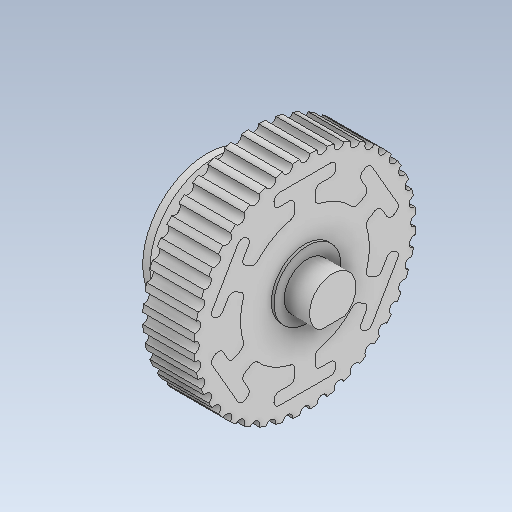
# Autodesk Inventor part: Rad ohne Antrieb
Saved by Autodesk Inventor 2026.4 (Build 304435030, 435C)
## iProperties
Created: 2026-11-20
Part Number: Rad ohne Antrieb
Material: Generisch
Document SubType Name: Modeling
Designer: weira
Density: 1 g/cm^3
Appearance: Vorgabe
Author: weira
Autodesk Inventor part; units mm, degrees
(part 1 of 2)
ref_plane "YZ Plane" through (0, 0, 0) normal (1, 0, 0) x (0, 1, 0)
ref_plane "XZ Plane" through (0, 0, 0) normal (0, 1, 0) x (-1, 0, 0)
ref_plane "XY Plane" through (0, 0, 0) normal (0, 0, 1) x (1, 0, 0)
sketch "Skizze1" plane through (0, 0, 0) normal (1, 0, 0) x (0, 1, 0)
  circle A0 centre (0, 0) radius 9.5511 construction
  line L0 (-27.1413, 20.191) -> (-18.5928, 20.191)
  line L1 (-18.5928, 20.191) -> (-18.5928, 11.6857)
  line L2 (-18.5928, 11.6857) -> (-27.1413, 11.6857)
  line L3 (-27.1413, 11.6857) -> (-27.1413, 20.191)
  circle A1 centre (0, 0) radius 8.6811 construction
  circle A2 centre (0, 0) radius 9.8211
  arc A3 (0.7095, 9.0476) -> (0.9041, 9.6681) centre (-0.61, 9.8021) ccw
  arc A4 (1.0279, 9.7672) -> (0.9041, 9.6681) centre (1.0264, 9.6422) ccw
  line L4 (0, 8.6811) -> (0, 7.1512) construction
  arc A5 (-0.9041, 9.6681) -> (-0.7095, 9.0476) centre (0.61, 9.8021) ccw
  arc A6 (-0.9041, 9.6681) -> (-1.0279, 9.7672) centre (-1.0264, 9.6422) ccw
  arc A7 (-0.7095, 9.0476) -> (0.7095, 9.0476) centre (0, 9.5511) ccw
  arc A8 (-2.0407, 9.6068) -> (-2.1278, 9.4743) centre (-2.0035, 9.4874) ccw
  arc A9 (-3.8474, 8.9155) -> (-3.9958, 8.9715) centre (-3.9557, 8.8531) ccw
  arc A10 (-2.1211, 8.824) -> (-2.1278, 9.4743) centre (-3.6092, 9.1339) ccw
  arc A11 (-3.8474, 8.9155) -> (-3.4706, 8.3855) centre (-2.4489, 9.5109) ccw
  arc A12 (-3.4706, 8.3855) -> (-2.1211, 8.824) centre (-2.9515, 9.0836) ccw
  arc A13 (-4.9094, 8.506) -> (-4.9513, 8.353) centre (-4.8372, 8.404) ccw
  arc A14 (-6.4142, 7.2902) -> (-6.5726, 7.2976) centre (-6.4979, 7.1974) ccw
  arc A15 (-4.744, 7.7367) -> (-4.9513, 8.353) centre (-6.2551, 7.5715) ccw
  arc A16 (-6.4142, 7.2902) -> (-5.892, 6.9026) centre (-5.2681, 8.2886) ccw
  arc A17 (-5.892, 6.9026) -> (-4.744, 7.7367) centre (-5.614, 7.727) ccw
  arc A18 (-7.2976, 6.5726) -> (-7.2902, 6.4142) centre (-7.1974, 6.4979) ccw
  arc A19 (-8.353, 4.9513) -> (-8.506, 4.9094) centre (-8.404, 4.8372) ccw
  arc A20 (-6.9026, 5.892) -> (-7.2902, 6.4142) centre (-8.2886, 5.2681) ccw
  arc A21 (-8.353, 4.9513) -> (-7.7367, 4.744) centre (-7.5715, 6.2551) ccw
  arc A22 (-7.7367, 4.744) -> (-6.9026, 5.892) centre (-7.727, 5.614) ccw
  arc A23 (-8.9715, 3.9958) -> (-8.9155, 3.8474) centre (-8.8531, 3.9557) ccw
  arc A24 (-9.4743, 2.1278) -> (-9.6068, 2.0407) centre (-9.4874, 2.0035) ccw
  arc A25 (-8.3855, 3.4706) -> (-8.9155, 3.8474) centre (-9.5109, 2.4489) ccw
  arc A26 (-9.4743, 2.1278) -> (-8.824, 2.1211) centre (-9.1339, 3.6092) ccw
  arc A27 (-8.824, 2.1211) -> (-8.3855, 3.4706) centre (-9.0836, 2.9515) ccw
  arc A28 (-9.7672, 1.0279) -> (-9.6681, 0.9041) centre (-9.6422, 1.0264) ccw
  arc A29 (-9.6681, -0.9041) -> (-9.7672, -1.0279) centre (-9.6422, -1.0264) ccw
  arc A30 (-9.0476, 0.7095) -> (-9.6681, 0.9041) centre (-9.8021, -0.61) ccw
  arc A31 (-9.6681, -0.9041) -> (-9.0476, -0.7095) centre (-9.8021, 0.61) ccw
  arc A32 (-9.0476, -0.7095) -> (-9.0476, 0.7095) centre (-9.5511, 0) ccw
  arc A33 (-9.6068, -2.0407) -> (-9.4743, -2.1278) centre (-9.4874, -2.0035) ccw
  arc A34 (-8.9155, -3.8474) -> (-8.9715, -3.9958) centre (-8.8531, -3.9557) ccw
  arc A35 (-8.824, -2.1211) -> (-9.4743, -2.1278) centre (-9.1339, -3.6092) ccw
  arc A36 (-8.9155, -3.8474) -> (-8.3855, -3.4706) centre (-9.5109, -2.4489) ccw
  arc A37 (-8.3855, -3.4706) -> (-8.824, -2.1211) centre (-9.0836, -2.9515) ccw
  arc A38 (-8.506, -4.9094) -> (-8.353, -4.9513) centre (-8.404, -4.8372) ccw
  arc A39 (-7.2902, -6.4142) -> (-7.2976, -6.5726) centre (-7.1974, -6.4979) ccw
  arc A40 (-7.7367, -4.744) -> (-8.353, -4.9513) centre (-7.5715, -6.2551) ccw
  arc A41 (-7.2902, -6.4142) -> (-6.9026, -5.892) centre (-8.2886, -5.2681) ccw
  arc A42 (-6.9026, -5.892) -> (-7.7367, -4.744) centre (-7.727, -5.614) ccw
  arc A43 (-6.5726, -7.2976) -> (-6.4142, -7.2902) centre (-6.4979, -7.1974) ccw
  arc A44 (-4.9513, -8.353) -> (-4.9094, -8.506) centre (-4.8372, -8.404) ccw
  arc A45 (-5.892, -6.9026) -> (-6.4142, -7.2902) centre (-5.2681, -8.2886) ccw
  arc A46 (-4.9513, -8.353) -> (-4.744, -7.7367) centre (-6.2551, -7.5715) ccw
  arc A47 (-4.744, -7.7367) -> (-5.892, -6.9026) centre (-5.614, -7.727) ccw
  arc A48 (-3.9958, -8.9715) -> (-3.8474, -8.9155) centre (-3.9557, -8.8531) ccw
  arc A49 (-2.1278, -9.4743) -> (-2.0407, -9.6068) centre (-2.0035, -9.4874) ccw
  arc A50 (-3.4706, -8.3855) -> (-3.8474, -8.9155) centre (-2.4489, -9.5109) ccw
  arc A51 (-2.1278, -9.4743) -> (-2.1211, -8.824) centre (-3.6092, -9.1339) ccw
  arc A52 (-2.1211, -8.824) -> (-3.4706, -8.3855) centre (-2.9515, -9.0836) ccw
  arc A53 (-1.0279, -9.7672) -> (-0.9041, -9.6681) centre (-1.0264, -9.6422) ccw
  arc A54 (0.9041, -9.6681) -> (1.0279, -9.7672) centre (1.0264, -9.6422) ccw
  arc A55 (-0.7095, -9.0476) -> (-0.9041, -9.6681) centre (0.61, -9.8021) ccw
  arc A56 (0.9041, -9.6681) -> (0.7095, -9.0476) centre (-0.61, -9.8021) ccw
  arc A57 (0.7095, -9.0476) -> (-0.7095, -9.0476) centre (0, -9.5511) ccw
  arc A58 (2.0407, -9.6068) -> (2.1278, -9.4743) centre (2.0035, -9.4874) ccw
  arc A59 (3.8474, -8.9155) -> (3.9958, -8.9715) centre (3.9557, -8.8531) ccw
  arc A60 (2.1211, -8.824) -> (2.1278, -9.4743) centre (3.6092, -9.1339) ccw
  arc A61 (3.8474, -8.9155) -> (3.4706, -8.3855) centre (2.4489, -9.5109) ccw
  arc A62 (3.4706, -8.3855) -> (2.1211, -8.824) centre (2.9515, -9.0836) ccw
  arc A63 (4.9094, -8.506) -> (4.9513, -8.353) centre (4.8372, -8.404) ccw
  arc A64 (6.4142, -7.2902) -> (6.5726, -7.2976) centre (6.4979, -7.1974) ccw
  arc A65 (4.744, -7.7367) -> (4.9513, -8.353) centre (6.2551, -7.5715) ccw
  arc A66 (6.4142, -7.2902) -> (5.892, -6.9026) centre (5.2681, -8.2886) ccw
  arc A67 (5.892, -6.9026) -> (4.744, -7.7367) centre (5.614, -7.727) ccw
  arc A68 (7.2976, -6.5726) -> (7.2902, -6.4142) centre (7.1974, -6.4979) ccw
  arc A69 (8.353, -4.9513) -> (8.506, -4.9094) centre (8.404, -4.8372) ccw
  arc A70 (6.9026, -5.892) -> (7.2902, -6.4142) centre (8.2886, -5.2681) ccw
  arc A71 (8.353, -4.9513) -> (7.7367, -4.744) centre (7.5715, -6.2551) ccw
  arc A72 (7.7367, -4.744) -> (6.9026, -5.892) centre (7.727, -5.614) ccw
  arc A73 (8.9715, -3.9958) -> (8.9155, -3.8474) centre (8.8531, -3.9557) ccw
  arc A74 (9.4743, -2.1278) -> (9.6068, -2.0407) centre (9.4874, -2.0035) ccw
  arc A75 (8.3855, -3.4706) -> (8.9155, -3.8474) centre (9.5109, -2.4489) ccw
  arc A76 (9.4743, -2.1278) -> (8.824, -2.1211) centre (9.1339, -3.6092) ccw
  arc A77 (8.824, -2.1211) -> (8.3855, -3.4706) centre (9.0836, -2.9515) ccw
  arc A78 (9.7672, -1.0279) -> (9.6681, -0.9041) centre (9.6422, -1.0264) ccw
  arc A79 (9.6681, 0.9041) -> (9.7672, 1.0279) centre (9.6422, 1.0264) ccw
  arc A80 (9.0476, -0.7095) -> (9.6681, -0.9041) centre (9.8021, 0.61) ccw
  arc A81 (9.6681, 0.9041) -> (9.0476, 0.7095) centre (9.8021, -0.61) ccw
  arc A82 (9.0476, 0.7095) -> (9.0476, -0.7095) centre (9.5511, 0) ccw
  arc A83 (9.6068, 2.0407) -> (9.4743, 2.1278) centre (9.4874, 2.0035) ccw
  arc A84 (8.9155, 3.8474) -> (8.9715, 3.9958) centre (8.8531, 3.9557) ccw
  arc A85 (8.824, 2.1211) -> (9.4743, 2.1278) centre (9.1339, 3.6092) ccw
  arc A86 (8.9155, 3.8474) -> (8.3855, 3.4706) centre (9.5109, 2.4489) ccw
  arc A87 (8.3855, 3.4706) -> (8.824, 2.1211) centre (9.0836, 2.9515) ccw
  arc A88 (8.506, 4.9094) -> (8.353, 4.9513) centre (8.404, 4.8372) ccw
  arc A89 (7.2902, 6.4142) -> (7.2976, 6.5726) centre (7.1974, 6.4979) ccw
  arc A90 (7.7367, 4.744) -> (8.353, 4.9513) centre (7.5715, 6.2551) ccw
  arc A91 (7.2902, 6.4142) -> (6.9026, 5.892) centre (8.2886, 5.2681) ccw
  arc A92 (6.9026, 5.892) -> (7.7367, 4.744) centre (7.727, 5.614) ccw
  arc A93 (6.5726, 7.2976) -> (6.4142, 7.2902) centre (6.4979, 7.1974) ccw
  arc A94 (4.9513, 8.353) -> (4.9094, 8.506) centre (4.8372, 8.404) ccw
  arc A95 (5.892, 6.9026) -> (6.4142, 7.2902) centre (5.2681, 8.2886) ccw
  arc A96 (4.9513, 8.353) -> (4.744, 7.7367) centre (6.2551, 7.5715) ccw
  arc A97 (4.744, 7.7367) -> (5.892, 6.9026) centre (5.614, 7.727) ccw
  arc A98 (3.9958, 8.9715) -> (3.8474, 8.9155) centre (3.9557, 8.8531) ccw
  arc A99 (2.1278, 9.4743) -> (2.0407, 9.6068) centre (2.0035, 9.4874) ccw
  arc A100 (3.4706, 8.3855) -> (3.8474, 8.9155) centre (2.4489, 9.5109) ccw
  arc A101 (2.1278, 9.4743) -> (2.1211, 8.824) centre (3.6092, 9.1339) ccw
  arc A102 (2.1211, 8.824) -> (3.4706, 8.3855) centre (2.9515, 9.0836) ccw
  circle A103 centre (0, 0) radius 12.0811
  point P0 (-2.6826, 8.2562)
  point P1 (-5.1026, 7.0232)
  point P2 (-7.0232, 5.1026)
  point P3 (-8.2562, 2.6826)
  point P4 (-8.6811, 0)
  point P5 (-8.2562, -2.6826)
  point P6 (-7.0232, -5.1026)
  point P7 (-5.1026, -7.0232)
  point P8 (-2.6826, -8.2562)
  point P9 (0, -8.6811)
  point P10 (2.6826, -8.2562)
  point P11 (5.1026, -7.0232)
  point P12 (7.0232, -5.1026)
  point P13 (8.2562, -2.6826)
  point P14 (8.6811, 0)
  point P15 (8.2562, 2.6826)
  point P16 (7.0232, 5.1026)
  point P17 (5.1026, 7.0232)
  point P18 (2.6826, 8.2562)
  point P19 (-22.511, 9.9251)
  point P20 (-23.5238, 9.7647)
  point P21 (-25.4789, 9.1295)
  point P22 (-26.3926, 8.6639)
  point P23 (-28.0557, 7.4556)
  point P24 (-28.7808, 6.7305)
  point P25 (-29.9891, 5.0674)
  point P26 (-30.4547, 4.1537)
  point P27 (-31.0899, 2.1986)
  point P28 (-31.2503, 1.1858)
  point P29 (-31.2503, -0.8699)
  point P30 (-31.0899, -1.8827)
  point P31 (-30.4547, -3.8378)
  point P32 (-29.9891, -4.7515)
  point P33 (-28.7808, -6.4146)
  point P34 (-28.0557, -7.1397)
  point P35 (-26.3926, -8.348)
  point P36 (-25.4789, -8.8135)
  point P37 (-23.5238, -9.4488)
  point P38 (-22.511, -9.6092)
  point P39 (-20.4553, -9.6092)
  point P40 (-19.4425, -9.4488)
  point P41 (-17.4874, -8.8135)
  point P42 (-16.5737, -8.348)
  point P43 (-14.9106, -7.1397)
  point P44 (-14.1855, -6.4146)
  point P45 (-12.9772, -4.7515)
  point P46 (-12.5117, -3.8378)
  point P47 (-11.8764, -1.8827)
  point P48 (-11.716, -0.8699)
  point P49 (-11.716, 1.1858)
  point P50 (-11.8764, 2.1986)
  point P51 (-12.5117, 4.1537)
  point P52 (-12.9772, 5.0674)
  point P53 (-14.1855, 6.7305)
  point P54 (-14.9106, 7.4556)
  point P55 (-16.5737, 8.6639)
  point P56 (-17.4874, 9.1295)
  point P57 (-19.4425, 9.7647)
  point P58 (-1.0279, 9.7672)
  point P59 (-2.0407, 9.6068)
  point P60 (-3.9958, 8.9715)
  point P61 (-4.9094, 8.506)
  point P62 (-6.5726, 7.2976)
  point P63 (-7.2976, 6.5726)
  point P64 (-8.506, 4.9094)
  point P65 (-8.9715, 3.9958)
  point P66 (-9.6068, 2.0407)
  point P67 (-9.7672, 1.0279)
  point P68 (-9.7672, -1.0279)
  point P69 (-9.6068, -2.0407)
  point P70 (-8.9715, -3.9958)
  point P71 (-8.506, -4.9094)
  point P72 (-7.2976, -6.5726)
  point P73 (-6.5726, -7.2976)
  point P74 (-4.9094, -8.506)
  point P75 (-3.9958, -8.9715)
  point P76 (-2.0407, -9.6068)
  point P77 (-1.0279, -9.7672)
  point P78 (1.0279, -9.7672)
  point P79 (2.0407, -9.6068)
  point P80 (3.9958, -8.9715)
  point P81 (4.9094, -8.506)
  point P82 (6.5726, -7.2976)
  point P83 (7.2976, -6.5726)
  point P84 (8.506, -4.9094)
  point P85 (8.9715, -3.9958)
  point P86 (9.6068, -2.0407)
  point P87 (9.7672, -1.0279)
  point P88 (9.7672, 1.0279)
  point P89 (9.6068, 2.0407)
  point P90 (8.9715, 3.9958)
  point P91 (8.506, 4.9094)
  point P92 (7.2976, 6.5726)
  point P93 (6.5726, 7.2976)
  point P94 (4.9094, 8.506)
  point P95 (3.9958, 8.9715)
  point P96 (2.0407, 9.6068)
  dimension "d2" = 19.1022
  dimension "d3" = 1.14
  dimension "d4" = 0.61
  dimension "d5" = 0.25
  dimension "d6" = 360
  dimension "d7" = 3.4
  constraints: 220 point on circle, 101 centre point, 5 coincident, 5 symmetric about line, 2 end point, 2 vertical alignment, 1 vertical, 353 other
  measures "d4" horizontal distance of A3.centre A7.centre
  measures "d5" diameter of A4
extrude "Extrusion1" add sketch "Skizze1" along normal mid plane 6.2 contours A79 A81 A82 A80 A78 A2 A74 A76 A77 A75 A73 A69 A71 A72 A70 A68 A64 A66 A67 A65 A63 A59 A61 A62 A60 A58 A54 A56 A57 A55 A53 A49 A51 A52 A50 A48 A44 A46 A47 A45 A43 A39 A41 A42 A40 A38 A34 A36 A37 A35 A33 A29 A31 A32 A30 A28 A24 A26 A27 A25 A23 A19 A21 A22 A20 A18 A14 A16 A17 A15 A13 A9 A11 A12 A10 A8 A6 A5 A7 A3 A4 A99 A101 A102 A100 A98 A94 A96 A97 A95 A93 A89 A91 A92 A90 A88 A84 A86 A87 A85 A83
sketch "Skizze2" plane through (-3.1, 0, 0) normal (-1, 0, 0) x (0, 0, 1)
  circle A0 centre (0, 0) radius 9.825
  circle A1 centre (0, 0) radius 12.5
  dimension "d14" = 19.65
  dimension "d15" = 25
  constraints: 2 centre point, 2 coincident
  measures "d14" diameter of A0
  measures "d15" diameter of A1
extrude "Extrusion2" add sketch "Skizze2" along normal blind 1.4 contours A0 | A1
mirror "Spiegeln1" about plane through (0, 0, 0) normal (1, 0, 0) of "Extrusion2"
sketch "Skizze5" plane through (4.5, 0, 0) normal (1, 0, 0) x (0, 0, -1)
  circle A0 centre (0, 0) radius 12.5 projected
  circle A1 centre (0, 0) radius 20
  dimension "d28" = 40
  constraints: 1 centre point, 1 coincident
  measures "d28" diameter of A1
extrude "Extrusion5" add sketch "Skizze5" along normal blind 10 contours A0 | A1
sketch "Skizze6" plane through (14.5, 0, 0) normal (1, 0, 0) x (0, 0, -1)
  line L0 (-5, -6) -> (5, -6)
  line L1 (5, -6) -> (5, 6)
  line L2 (5, 6) -> (-5, 6)
  line L3 (-5, 6) -> (-5, -6)
  line L4 (-5, -6) -> (5, 6) construction
  line L5 (5, -6) -> (-5, 6) construction
  circle A0 centre (0, 0) radius 7.8102
  circle A1 centre (0, 0) radius 8.5
  dimension "d33" = 15.6205
  dimension "d31" = 12
  dimension "d32" = 10
  dimension "d34" = 17
  constraints: 12 end point, 2 coincident, 2 midpoint, 2 parallel, 1 centre point, 1 horizontal, 1 perpendicular, 3 other
  measures "d31" distance of L2.end L0.start
  measures "d32" distance of L1.end L2.end
  measures "d34" diameter of A1
extrude "Extrusion6" cut sketch "Skizze6" against normal blind 8.8 contours L3 L2 L1 L0 | A0 L3 | L0 A0 | L1 A0 | A0 L2 | A1
sketch "Skizze7" plane through (-4.5, 0, 0) normal (-1, 0, 0) x (0, 0, 1)
  arc A0 (2.0768, -37.6136) -> (2.0768, -39.8496) centre (1.0768, -38.7316) ccw
  arc A1 (-2.7232, -41.142) -> (-2.7232, -36.3212) centre (1.0768, -38.7316) ccw
  line L0 (-2.7232, -36.3212) -> (-2.7232, -41.142)
  circle A2 centre (0, 0) radius 12.5 projected
  arc A3 (1, 1.118) -> (1, -1.118) centre (0, 0) ccw
  arc A4 (-3.8, -2.4104) -> (-3.8, 2.4104) centre (0, 0) ccw
  line L1 (-3.8, 2.4104) -> (-3.8, -2.4104)
  constraints: 8 point on circle, 4 centre point, 4 end point
extrude "Extrusion7" cut sketch "Skizze7" against normal blind 8.2 contours L1 A4
extrude "Extrusion8" add sketch "Skizze7" against normal blind 8.2 separate body contours L1 A4
extrude "Extrusion9" add sketch "Skizze7" along normal blind 5.5 contours L1 A4 bodies 2
sketch "Skizze8" plane through (5.7, 0, 0) normal (1, 0, 0) x (0, 0, -1)
  arc A0 (0.2064, 25.9208) -> (2.4424, 25.9208) centre (1.3244, 24.9208) ccw
  line L0 (2.4424, 25.9208) -> (0.2064, 25.9208)
  arc A1 (1, 1.118) -> (1, -1.118) centre (0, 0) ccw
  line L1 (1, -1.118) -> (1, 1.118)
  constraints: 4 end point, 4 point on circle, 2 centre point
extrude "Extrusion10" cut sketch "Skizze8" against normal blind 10.2 contours L1 A1 bodies 1 2
sketch "Skizze9" plane through (-4.5, 0, 0) normal (-1, 0, 0) x (0, 0, 1)
  line L0 (-3.8, 2.4104) -> (-3.8, -2.4104) projected
  arc A0 (-3.8, -2.4104) -> (-3.8, 2.4104) centre (0, 0) ccw projected
  circle A1 centre (0.2217, 0) radius 6.5
  arc A2 (-3.8, -2.4104) -> (-3.8, 2.4104) centre (0, 0) ccw projected
  dimension "d45" = 13
  constraints: 1 centre point
  measures "d45" diameter of A1
extrude "Extrusion11" add sketch "Skizze9" along normal blind 0.5 bodies 1
sketch "Skizze12" plane through (4.5, 0, 0) normal (-1, 0, 0) x (0, 0, 1)
  circle A0 centre (0, 0) radius 12.5 projected
  line L0 (15.5, 2) -> (10.5, 2)
  line L1 (10.5, 2) -> (10.5, -2)
  line L2 (10.5, -2) -> (15.5, -2)
  line L3 (15.5, -2) -> (15.5, 2)
  line L4 (21.7574, 0) -> (-22.368, 0) construction
  line L5 (-31.1931, 0) -> (30.5824, 0) projected
  line L6 (17.9, 6) -> (15.5, 6)
  line L7 (15.5, 6) -> (15.5, -6)
  line L8 (15.5, -6) -> (17.9, -6)
  line L9 (17.9, -6) -> (17.9, 6)
  line L10 (9.4821, 12.4234) -> (6.0179, 14.4234)
  line L11 (3.7538, 18.5019) -> (2.5538, 16.4234)
  line L12 (6.0179, 14.4234) -> (3.5179, 10.0933)
  line L13 (6.9821, 8.0933) -> (9.4821, 12.4234)
  line L14 (12.9462, 10.4234) -> (14.1462, 12.5019)
  line L15 (2.5538, 16.4234) -> (12.9462, 10.4234)
  line L16 (14.1462, 12.5019) -> (3.7538, 18.5019)
  line L17 (3.5179, 10.0933) -> (6.9821, 8.0933)
  line L18 (-6.0179, 14.4234) -> (-9.4821, 12.4234)
  line L19 (-14.1462, 12.5019) -> (-12.9462, 10.4234)
  line L20 (-9.4821, 12.4234) -> (-6.9821, 8.0933)
  line L21 (-3.5179, 10.0933) -> (-6.0179, 14.4234)
  line L22 (-2.5538, 16.4234) -> (-3.7538, 18.5019)
  line L23 (-12.9462, 10.4234) -> (-2.5538, 16.4234)
  line L24 (-3.7538, 18.5019) -> (-14.1462, 12.5019)
  line L25 (-6.9821, 8.0933) -> (-3.5179, 10.0933)
  line L26 (-15.5, 2) -> (-15.5, -2)
  line L27 (-17.9, -6) -> (-15.5, -6)
  line L28 (-15.5, -2) -> (-10.5, -2)
  line L29 (-10.5, 2) -> (-15.5, 2)
  line L30 (-15.5, 6) -> (-17.9, 6)
  line L31 (-15.5, -6) -> (-15.5, 6)
  line L32 (-17.9, 6) -> (-17.9, -6)
  line L33 (-10.5, -2) -> (-10.5, 2)
  line L34 (-9.4821, -12.4234) -> (-6.0179, -14.4234)
  line L35 (-3.7538, -18.5019) -> (-2.5538, -16.4234)
  line L36 (-6.0179, -14.4234) -> (-3.5179, -10.0933)
  line L37 (-6.9821, -8.0933) -> (-9.4821, -12.4234)
  line L38 (-12.9462, -10.4234) -> (-14.1462, -12.5019)
  line L39 (-2.5538, -16.4234) -> (-12.9462, -10.4234)
  line L40 (-14.1462, -12.5019) -> (-3.7538, -18.5019)
  line L41 (-3.5179, -10.0933) -> (-6.9821, -8.0933)
  line L42 (6.0179, -14.4234) -> (9.4821, -12.4234)
  line L43 (14.1462, -12.5019) -> (12.9462, -10.4234)
  line L44 (9.4821, -12.4234) -> (6.9821, -8.0933)
  line L45 (3.5179, -10.0933) -> (6.0179, -14.4234)
  line L46 (2.5538, -16.4234) -> (3.7538, -18.5019)
  line L47 (12.9462, -10.4234) -> (2.5538, -16.4234)
  line L48 (3.7538, -18.5019) -> (14.1462, -12.5019)
  line L49 (6.9821, -8.0933) -> (3.5179, -10.0933)
  circle A1 centre (0, 0) radius 20 projected
  circle A2 centre (0, 0) radius 12.5 projected
  point P0 (10.8787, 18.8424)
  point P1 (-10.8787, 18.8424)
  point P2 (-21.7574, 0)
  point P3 (-10.8787, -18.8424)
  point P4 (10.8787, -18.8424)
  point P5 (-15.5, 2)
  point P6 (-12.339, 2)
  point P7 (-7.9015, 9.6859)
  point P8 (-9.4821, 12.4234)
  point P9 (-6.0179, 14.4234)
  point P10 (-4.4374, 11.6859)
  point P11 (4.4374, 11.6859)
  point P12 (6.0179, 14.4234)
  point P13 (9.4821, 12.4234)
  point P14 (7.9015, 9.6859)
  point P15 (12.339, 2)
  point P16 (15.5, -2)
  point P17 (12.339, -2)
  point P18 (7.9015, -9.6859)
  point P19 (9.4821, -12.4234)
  point P20 (6.0179, -14.4234)
  point P21 (4.4374, -11.6859)
  point P22 (-4.4374, -11.6859)
  point P23 (-6.0179, -14.4234)
  point P24 (-9.4821, -12.4234)
  point P25 (-7.9015, -9.6859)
  point P26 (-12.339, -2)
  point P27 (-15.5, -2)
  dimension "d53" = 4
  dimension "d54" = 3
  dimension "d55" = 2
  dimension "d56" = 0
  dimension "d57" = 5
  dimension "d58" = 2.4
  dimension "d59" = 0
  dimension "d60" = 12
  dimension "d61" = 6
  dimension "d64" = 360
  constraints: 98 end point, 4 parallel, 3 horizontal, 2 perpendicular, 103 other
  measures "d53" distance between parallel lines of L2 L0
  measures "d54" distance edge to line of A0 L3
  measures "d55" distance between parallel lines of L4 L2
  measures "d56" distance between parallel lines of L5 L4
  measures "d57" distance of L1.end L2.end
  measures "d58" distance between parallel lines of L7 L9
  measures "d59" distance between parallel lines of L3 L7
  measures "d60" distance between parallel lines of L8 L6
  measures "d61" distance between parallel lines of L4 L8
extrude "Extrusion12" cut sketch "Skizze12" against normal through all contours A0 L13 L15 L14 L16 L11 L12 L21 L23 L22 L24 L19 L20 L29 L31 L30 L32 L5 A1 L9 L6 L7 L0 | L2 L7 L8 L9 L5 A1 L32 L27 L31 L28 A0 L37 L39 L38 L40 L35 L36 L45 L47 L46 L48 L43 L44 bodies 1
fillet "Rundung1" radius 1 8 edges at (9.5, 18.5019, 3.7538) (9.5, 16.4234, 2.5538) (9.5, 12.5019, 14.1462) (9.5, 10.4234, 12.9462) (9.5, 14.4234, 6.0179) (9.5, 11.6859, 4.4374) (9.5, 9.6859, 7.9015) (9.5, 12.4234, 9.4821)
pattern_circular "Runde Anordnung1" count 6 over 360 about axis through (-10, 0, 0) along (1, 0, 0) of "Rundung1"
sketch "Skizze13" plane through (4.5, 0, 0) normal (-1, 0, 0) x (0, 0, 1)
  circle A0 centre (0, 0) radius 20
  arc A1 (12.0801, 10.9234) -> (13.4462, 11.2894) centre (12.5801, 11.7894) ccw projected
  line L0 (13.4462, 11.2894) -> (13.6462, 11.6358) projected
  arc A2 (13.6462, 11.6358) -> (13.2801, 13.0019) centre (12.7801, 12.1358) ccw projected
  line L1 (13.2801, 13.0019) -> (4.6199, 18.0019) projected
  arc A3 (4.6199, 18.0019) -> (3.2538, 17.6358) centre (4.1199, 17.1358) ccw projected
  line L2 (3.2538, 17.6358) -> (3.0538, 17.2894) projected
  arc A4 (3.0538, 17.2894) -> (3.4199, 15.9234) centre (3.9199, 16.7894) ccw projected
  arc A5 (5.5179, 13.5574) -> (5.1519, 14.9234) centre (4.6519, 14.0574) ccw projected
  line L3 (5.5179, 13.5574) -> (4.8492, 12.399) projected
  arc A6 (3.6881, 11.9435) -> (4.8492, 12.399) centre (3.9831, 12.899) ccw projected
  arc A7 (8.4994, 9.1658) -> (3.6881, 11.9435) centre (0, 0) ccw projected
  arc A8 (8.3133, 10.399) -> (8.4994, 9.1658) centre (9.1793, 9.899) ccw projected
  line L4 (8.3133, 10.399) -> (8.9821, 11.5574) projected
  arc A9 (10.3481, 11.9234) -> (8.9821, 11.5574) centre (9.8481, 11.0574) ccw projected
  arc A10 (-3.4199, 15.9234) -> (-3.0538, 17.2894) centre (-3.9199, 16.7894) ccw projected
  line L5 (-3.0538, 17.2894) -> (-3.2538, 17.6358) projected
  arc A11 (-3.2538, 17.6358) -> (-4.6199, 18.0019) centre (-4.1199, 17.1358) ccw projected
  line L6 (-4.6199, 18.0019) -> (-13.2801, 13.0019) projected
  arc A12 (-13.2801, 13.0019) -> (-13.6462, 11.6358) centre (-12.7801, 12.1358) ccw projected
  line L7 (-13.6462, 11.6358) -> (-13.4462, 11.2894) projected
  arc A13 (-13.4462, 11.2894) -> (-12.0801, 10.9234) centre (-12.5801, 11.7894) ccw projected
  arc A14 (-8.9821, 11.5574) -> (-10.3481, 11.9234) centre (-9.8481, 11.0574) ccw projected
  line L8 (-8.9821, 11.5574) -> (-8.3133, 10.399) projected
  arc A15 (-8.4994, 9.1658) -> (-8.3133, 10.399) centre (-9.1793, 9.899) ccw projected
  arc A16 (-3.6881, 11.9435) -> (-8.4994, 9.1658) centre (0, 0) ccw projected
  arc A17 (-4.8492, 12.399) -> (-3.6881, 11.9435) centre (-3.9831, 12.899) ccw projected
  line L9 (-4.8492, 12.399) -> (-5.5179, 13.5574) projected
  arc A18 (-5.1519, 14.9234) -> (-5.5179, 13.5574) centre (-4.6519, 14.0574) ccw projected
  arc A19 (-15.5, 5) -> (-16.5, 6) centre (-16.5, 5) ccw projected
  line L10 (-16.5, 6) -> (-16.9, 6) projected
  arc A20 (-16.9, 6) -> (-17.9, 5) centre (-16.9, 5) ccw projected
  line L11 (-17.9, 5) -> (-17.9, -5) projected
  arc A21 (-17.9, -5) -> (-16.9, -6) centre (-16.9, -5) ccw projected
  line L12 (-16.9, -6) -> (-16.5, -6) projected
  arc A22 (-16.5, -6) -> (-15.5, -5) centre (-16.5, -5) ccw projected
  arc A23 (-14.5, -2) -> (-15.5, -3) centre (-14.5, -3) ccw projected
  line L13 (-14.5, -2) -> (-13.1624, -2) projected
  arc A24 (-12.1875, -2.7778) -> (-13.1624, -2) centre (-13.1624, -3) ccw projected
  arc A25 (-12.1875, 2.7778) -> (-12.1875, -2.7778) centre (0, 0) ccw projected
  arc A26 (-13.1624, 2) -> (-12.1875, 2.7778) centre (-13.1624, 3) ccw projected
  line L14 (-13.1624, 2) -> (-14.5, 2) projected
  arc A27 (-15.5, 3) -> (-14.5, 2) centre (-14.5, 3) ccw projected
  arc A28 (-12.0801, -10.9234) -> (-13.4462, -11.2894) centre (-12.5801, -11.7894) ccw projected
  line L15 (-13.4462, -11.2894) -> (-13.6462, -11.6358) projected
  arc A29 (-13.6462, -11.6358) -> (-13.2801, -13.0019) centre (-12.7801, -12.1358) ccw projected
  line L16 (-13.2801, -13.0019) -> (-4.6199, -18.0019) projected
  arc A30 (-4.6199, -18.0019) -> (-3.2538, -17.6358) centre (-4.1199, -17.1358) ccw projected
  line L17 (-3.2538, -17.6358) -> (-3.0538, -17.2894) projected
  arc A31 (-3.0538, -17.2894) -> (-3.4199, -15.9234) centre (-3.9199, -16.7894) ccw projected
  arc A32 (-5.5179, -13.5574) -> (-5.1519, -14.9234) centre (-4.6519, -14.0574) ccw projected
  line L18 (-5.5179, -13.5574) -> (-4.8492, -12.399) projected
  arc A33 (-3.6881, -11.9435) -> (-4.8492, -12.399) centre (-3.9831, -12.899) ccw projected
  arc A34 (-8.4994, -9.1658) -> (-3.6881, -11.9435) centre (0, 0) ccw projected
  arc A35 (-8.3133, -10.399) -> (-8.4994, -9.1658) centre (-9.1793, -9.899) ccw projected
  line L19 (-8.3133, -10.399) -> (-8.9821, -11.5574) projected
  arc A36 (-10.3481, -11.9234) -> (-8.9821, -11.5574) centre (-9.8481, -11.0574) ccw projected
  arc A37 (3.4199, -15.9234) -> (3.0538, -17.2894) centre (3.9199, -16.7894) ccw projected
  line L20 (3.0538, -17.2894) -> (3.2538, -17.6358) projected
  arc A38 (3.2538, -17.6358) -> (4.6199, -18.0019) centre (4.1199, -17.1358) ccw projected
  line L21 (4.6199, -18.0019) -> (13.2801, -13.0019) projected
  arc A39 (13.2801, -13.0019) -> (13.6462, -11.6358) centre (12.7801, -12.1358) ccw projected
  line L22 (13.6462, -11.6358) -> (13.4462, -11.2894) projected
  arc A40 (13.4462, -11.2894) -> (12.0801, -10.9234) centre (12.5801, -11.7894) ccw projected
  arc A41 (8.9821, -11.5574) -> (10.3481, -11.9234) centre (9.8481, -11.0574) ccw projected
  line L23 (8.9821, -11.5574) -> (8.3133, -10.399) projected
  arc A42 (8.4994, -9.1658) -> (8.3133, -10.399) centre (9.1793, -9.899) ccw projected
  arc A43 (3.6881, -11.9435) -> (8.4994, -9.1658) centre (0, 0) ccw projected
  arc A44 (4.8492, -12.399) -> (3.6881, -11.9435) centre (3.9831, -12.899) ccw projected
  line L24 (4.8492, -12.399) -> (5.5179, -13.5574) projected
  arc A45 (5.1519, -14.9234) -> (5.5179, -13.5574) centre (4.6519, -14.0574) ccw projected
  arc A46 (15.5, -5) -> (16.5, -6) centre (16.5, -5) ccw projected
  line L25 (16.5, -6) -> (16.9, -6) projected
  arc A47 (16.9, -6) -> (17.9, -5) centre (16.9, -5) ccw projected
  line L26 (17.9, -5) -> (17.9, 5) projected
  arc A48 (17.9, 5) -> (16.9, 6) centre (16.9, 5) ccw projected
  line L27 (16.9, 6) -> (16.5, 6) projected
  arc A49 (16.5, 6) -> (15.5, 5) centre (16.5, 5) ccw projected
  arc A50 (14.5, 2) -> (15.5, 3) centre (14.5, 3) ccw projected
  line L28 (14.5, 2) -> (13.1624, 2) projected
  arc A51 (12.1875, 2.7778) -> (13.1624, 2) centre (13.1624, 3) ccw projected
  arc A52 (12.1875, -2.7778) -> (12.1875, 2.7778) centre (0, 0) ccw projected
  arc A53 (13.1624, -2) -> (12.1875, -2.7778) centre (13.1624, -3) ccw projected
  line L29 (13.1624, -2) -> (14.5, -2) projected
  arc A54 (15.5, -3) -> (14.5, -2) centre (14.5, -3) ccw projected
  circle A55 centre (0, 0) radius 12.5 projected
  circle A56 centre (20, 0) radius 1
  circle A57 centre (19.7538, 3.1287) radius 1
  circle A58 centre (19.0211, 6.1803) radius 1
  circle A59 centre (17.8201, 9.0798) radius 1
  circle A60 centre (16.1803, 11.7557) radius 1
  circle A61 centre (14.1421, 14.1421) radius 1
  circle A62 centre (11.7557, 16.1803) radius 1
  circle A63 centre (9.0798, 17.8201) radius 1
  circle A64 centre (6.1803, 19.0211) radius 1
  circle A65 centre (3.1287, 19.7538) radius 1
  circle A66 centre (0, 20) radius 1
  circle A67 centre (-3.1287, 19.7538) radius 1
  circle A68 centre (-6.1803, 19.0211) radius 1
  circle A69 centre (-9.0798, 17.8201) radius 1
  circle A70 centre (-11.7557, 16.1803) radius 1
  circle A71 centre (-14.1421, 14.1421) radius 1
  circle A72 centre (-16.1803, 11.7557) radius 1
  circle A73 centre (-17.8201, 9.0798) radius 1
  circle A74 centre (-19.0211, 6.1803) radius 1
  circle A75 centre (-19.7538, 3.1287) radius 1
  circle A76 centre (-20, 0) radius 1
  circle A77 centre (-19.7538, -3.1287) radius 1
  circle A78 centre (-19.0211, -6.1803) radius 1
  circle A79 centre (-17.8201, -9.0798) radius 1
  circle A80 centre (-16.1803, -11.7557) radius 1
  circle A81 centre (-14.1421, -14.1421) radius 1
  circle A82 centre (-11.7557, -16.1803) radius 1
  circle A83 centre (-9.0798, -17.8201) radius 1
  circle A84 centre (-6.1803, -19.0211) radius 1
  circle A85 centre (-3.1287, -19.7538) radius 1
  circle A86 centre (0, -20) radius 1
  circle A87 centre (3.1287, -19.7538) radius 1
  circle A88 centre (6.1803, -19.0211) radius 1
  circle A89 centre (9.0798, -17.8201) radius 1
  circle A90 centre (11.7557, -16.1803) radius 1
  circle A91 centre (14.1421, -14.1421) radius 1
  circle A92 centre (16.1803, -11.7557) radius 1
  circle A93 centre (17.8201, -9.0798) radius 1
  circle A94 centre (19.0211, -6.1803) radius 1
  circle A95 centre (19.7538, -3.1287) radius 1
  line L30 (3.4199, 15.9234) -> (5.1519, 14.9234) projected
  line L31 (10.3481, 11.9234) -> (12.0801, 10.9234) projected
  line L32 (15.5, 5) -> (15.5, 3) projected
  line L33 (15.5, -3) -> (15.5, -5) projected
  line L34 (12.0801, -10.9234) -> (10.3481, -11.9234) projected
  line L35 (5.1519, -14.9234) -> (3.4199, -15.9234) projected
  line L36 (-3.4199, -15.9234) -> (-5.1519, -14.9234) projected
  line L37 (-10.3481, -11.9234) -> (-12.0801, -10.9234) projected
  line L38 (-15.5, -5) -> (-15.5, -3) projected
  line L39 (-15.5, 3) -> (-15.5, 5) projected
  line L40 (-12.0801, 10.9234) -> (-10.3481, 11.9234) projected
  line L41 (-5.1519, 14.9234) -> (-3.4199, 15.9234) projected
  point P0 (19.5727, -4.1122)
  point P1 (19.8855, -2.1374)
  point P2 (19.975, -0.9997)
  point P3 (19.975, 0.9997)
  point P4 (19.8855, 2.1374)
  point P5 (19.5727, 4.1122)
  point P6 (19.3063, 5.2219)
  point P7 (18.6884, 7.1234)
  point P8 (18.2517, 8.1777)
  point P9 (17.344, 9.9592)
  point P10 (16.7477, 10.9322)
  point P11 (15.5725, 12.5498)
  point P12 (14.8313, 13.4176)
  point P13 (13.4176, 14.8313)
  point P14 (12.5498, 15.5725)
  point P15 (10.9322, 16.7477)
  point P16 (9.9592, 17.344)
  point P17 (8.1777, 18.2517)
  point P18 (7.1234, 18.6884)
  point P19 (5.2219, 19.3063)
  point P20 (4.1122, 19.5727)
  point P21 (2.1374, 19.8855)
  point P22 (0.9997, 19.975)
  point P23 (-0.9997, 19.975)
  point P24 (-2.1374, 19.8855)
  point P25 (-4.1122, 19.5727)
  point P26 (-5.2219, 19.3063)
  point P27 (-7.1234, 18.6884)
  point P28 (-8.1777, 18.2517)
  point P29 (-9.9592, 17.344)
  point P30 (-10.9322, 16.7477)
  point P31 (-12.5498, 15.5725)
  point P32 (-13.4176, 14.8313)
  point P33 (-14.8313, 13.4176)
  point P34 (-15.5725, 12.5498)
  point P35 (-16.7477, 10.9322)
  point P36 (-17.344, 9.9592)
  point P37 (-18.2517, 8.1777)
  point P38 (-18.6884, 7.1234)
  point P39 (-19.3063, 5.2219)
  point P40 (-19.5727, 4.1122)
  point P41 (-19.8855, 2.1374)
  point P42 (-19.975, 0.9997)
  point P43 (-19.975, -0.9997)
  point P44 (-19.8855, -2.1374)
  point P45 (-19.5727, -4.1122)
  point P46 (-19.3063, -5.2219)
  point P47 (-18.6884, -7.1234)
  point P48 (-18.2517, -8.1777)
  point P49 (-17.344, -9.9592)
  point P50 (-16.7477, -10.9322)
  point P51 (-15.5725, -12.5498)
  point P52 (-14.8313, -13.4176)
  point P53 (-13.4176, -14.8313)
  point P54 (-12.5498, -15.5725)
  point P55 (-10.9322, -16.7477)
  point P56 (-9.9592, -17.344)
  point P57 (-8.1777, -18.2517)
  point P58 (-7.1234, -18.6884)
  point P59 (-5.2219, -19.3063)
  point P60 (-4.1122, -19.5727)
  point P61 (-2.1374, -19.8855)
  point P62 (-0.9997, -19.975)
  point P63 (0.9997, -19.975)
  point P64 (2.1374, -19.8855)
  point P65 (4.1122, -19.5727)
  point P66 (5.2219, -19.3063)
  point P67 (7.1234, -18.6884)
  point P68 (8.1777, -18.2517)
  point P69 (9.9592, -17.344)
  point P70 (10.9322, -16.7477)
  point P71 (12.5498, -15.5725)
  point P72 (13.4176, -14.8313)
  point P73 (14.8313, -13.4176)
  point P74 (15.5725, -12.5498)
  point P75 (16.7477, -10.9322)
  point P76 (17.344, -9.9592)
  point P77 (18.2517, -8.1777)
  point P78 (18.6884, -7.1234)
  point P79 (19.3063, -5.2219)
  dimension "d68" = 40
  dimension "d73" = 2
  dimension "d76" = 360
  constraints: 40 centre point, 1 coincident, 84 other
  measures "d73" diameter of A56
extrude "Extrusion13" add sketch "Skizze13" against normal blind 10 separate body contours A56 A0 A95 A94 A93 A92 A91 A90 A89 A88 A87 A86 A85 A84 A83 A82 A81 A80 A79 A78 A77 A76 A75 A74 A73 A72 A71 A70 A69 A68 A67 A66 A65 A64 A63 A62 A61 A60 A59 A58 A57
sketch "Skizze14" plane through (-10, 0, 0) normal (-1, 0, 0) x (0, 0, 1)
  line L0 (-3.8, 2.4104) -> (-3.8, -2.4104) projected
  arc A0 (-3.8, -2.4104) -> (-3.8, 2.4104) centre (0, 0) ccw projected
extrude "Extrusion14" cut sketch "Skizze14" against normal through all bodies 1 2
sketch "Skizze15" plane through (5.7, 0, 0) normal (1, 0, 0) x (0, 0, -1)
  circle A0 centre (-0.2217, 0) radius 6.5 projected
  line L0 (3.8, 2.4104) -> (3.8, -2.4104) projected
  arc A1 (3.8, 2.4104) -> (3.8, -2.4104) centre (0, 0) ccw projected
  circle A2 centre (0, 0) radius 8.5 projected
extrude "Extrusion15" add sketch "Skizze15" along normal up to surface (8.8 mm away) contours A0 | A2 bodies 1
sketch "Skizze16" plane through (14.5, 0, 0) normal (1, 0, 0) x (0, 0, -1)
  circle A0 centre (-0.2217, 0) radius 6.5 projected
  arc A1 (3.8, 2.4104) -> (3.8, -2.4104) centre (0, 0) ccw projected
  line L0 (3.8, -2.4104) -> (3.8, 2.4104) projected
extrude "Extrusion16" add sketch "Skizze16" along normal blind 0.5 separate body
sketch "Skizze17" plane through (-5, 0, 0.2217) normal (-1, 0, 0) x (0, 0, 1)
  circle A0 centre (0, 0) radius 6.5 projected
  line L0 (-4.0217, -2.4104) -> (-4.0217, 2.4104) projected
  arc A1 (-4.0217, -2.4104) -> (-4.0217, 2.4104) centre (-0.2217, 0) ccw projected
extrude "Extrusion17" add sketch "Skizze17" along normal blind 4.9 and the other way blind 24.9 separate body contours L0 A1
sketch "Skizze18" plane through (14.5, 0, 0) normal (1, 0, 0) x (0, 0, -1)
  arc A0 (-13.4777, 86.5548) -> (-13.3881, 85.417) centre (6.4973, 87.5544) ccw
  arc A1 (-13.0753, 83.4423) -> (-13.3881, 85.417) centre (-13.2564, 84.4258) ccw
  arc A2 (-13.0753, 83.4423) -> (-12.8089, 82.3326) centre (6.4973, 87.5544) ccw
  arc A3 (-12.1911, 80.4311) -> (-12.8089, 82.3326) centre (-12.5238, 81.3741) ccw
  arc A4 (-12.1911, 80.4311) -> (-11.7544, 79.3767) centre (6.4973, 87.5544) ccw
  arc A5 (-10.8467, 77.5953) -> (-11.7544, 79.3767) centre (-11.3228, 78.4746) ccw
  arc A6 (-10.8467, 77.5953) -> (-10.2504, 76.6222) centre (6.4973, 87.5544) ccw
  arc A7 (-9.0752, 75.0047) -> (-10.2504, 76.6222) centre (-9.683, 75.7987) ccw
  arc A8 (-9.0752, 75.0047) -> (-8.334, 74.1369) centre (6.4973, 87.5544) ccw
  arc A9 (-6.9202, 72.7231) -> (-8.334, 74.1369) centre (-7.6448, 73.4123) ccw
  arc A10 (-6.9202, 72.7231) -> (-6.0524, 71.9819) centre (6.4973, 87.5544) ccw
  arc A11 (-4.4349, 70.8067) -> (-6.0524, 71.9819) centre (-5.2584, 71.3741) ccw
  arc A12 (-4.4349, 70.8067) -> (-3.4618, 70.2104) centre (6.4973, 87.5544) ccw
  arc A13 (-1.6804, 69.3027) -> (-3.4618, 70.2104) centre (-2.5825, 69.7343) ccw
  arc A14 (-1.6804, 69.3027) -> (-0.626, 68.866) centre (6.4973, 87.5544) ccw
  arc A15 (1.2755, 68.2482) -> (-0.626, 68.866) centre (0.317, 68.5333) ccw
  arc A16 (1.2755, 68.2482) -> (2.3852, 67.9818) centre (6.4973, 87.5544) ccw
  arc A17 (4.3599, 67.669) -> (2.3852, 67.9818) centre (3.3687, 67.8007) ccw
  arc A18 (4.3599, 67.669) -> (5.4977, 67.5794) centre (6.4973, 87.5544) ccw
  arc A19 (7.497, 67.5794) -> (5.4977, 67.5794) centre (6.4973, 67.5544) ccw
  arc A20 (7.497, 67.5794) -> (8.6347, 67.669) centre (6.4973, 87.5544) ccw
  arc A21 (10.6095, 67.9818) -> (8.6347, 67.669) centre (9.626, 67.8007) ccw
  arc A22 (10.6095, 67.9818) -> (11.7192, 68.2482) centre (6.4973, 87.5544) ccw
  arc A23 (13.6207, 68.866) -> (11.7192, 68.2482) centre (12.6777, 68.5333) ccw
  arc A24 (13.6207, 68.866) -> (14.6751, 69.3027) centre (6.4973, 87.5544) ccw
  arc A25 (16.4565, 70.2104) -> (14.6751, 69.3027) centre (15.5772, 69.7343) ccw
  arc A26 (16.4565, 70.2104) -> (17.4296, 70.8067) centre (6.4973, 87.5544) ccw
  arc A27 (19.0471, 71.9819) -> (17.4296, 70.8067) centre (18.2531, 71.3741) ccw
  arc A28 (19.0471, 71.9819) -> (19.9149, 72.7231) centre (6.4973, 87.5544) ccw
  arc A29 (21.3287, 74.1369) -> (19.9149, 72.7231) centre (20.6395, 73.4123) ccw
  arc A30 (21.3287, 74.1369) -> (22.0699, 75.0047) centre (6.4973, 87.5544) ccw
  arc A31 (23.2451, 76.6222) -> (22.0699, 75.0047) centre (22.6777, 75.7987) ccw
  arc A32 (23.2451, 76.6222) -> (23.8414, 77.5953) centre (6.4973, 87.5544) ccw
  arc A33 (24.7491, 79.3767) -> (23.8414, 77.5953) centre (24.3175, 78.4746) ccw
  arc A34 (24.7491, 79.3767) -> (25.1858, 80.4311) centre (6.4973, 87.5544) ccw
  arc A35 (25.8036, 82.3326) -> (25.1858, 80.4311) centre (25.5185, 81.3741) ccw
  arc A36 (25.8036, 82.3326) -> (26.07, 83.4423) centre (6.4973, 87.5544) ccw
  arc A37 (26.3828, 85.417) -> (26.07, 83.4423) centre (26.2511, 84.4258) ccw
  arc A38 (26.3828, 85.417) -> (26.4723, 86.5548) centre (6.4973, 87.5544) ccw
  arc A39 (26.4723, 88.5541) -> (26.4723, 86.5548) centre (26.4973, 87.5544) ccw
  arc A40 (26.4723, 88.5541) -> (26.3828, 89.6918) centre (6.4973, 87.5544) ccw
  arc A41 (26.07, 91.6666) -> (26.3828, 89.6918) centre (26.2511, 90.6831) ccw
  arc A42 (26.07, 91.6666) -> (25.8036, 92.7763) centre (6.4973, 87.5544) ccw
  arc A43 (25.1858, 94.6778) -> (25.8036, 92.7763) centre (25.5185, 93.7348) ccw
  arc A44 (25.1858, 94.6778) -> (24.7491, 95.7322) centre (6.4973, 87.5544) ccw
  arc A45 (23.8414, 97.5136) -> (24.7491, 95.7322) centre (24.3175, 96.6343) ccw
  arc A46 (23.8414, 97.5136) -> (23.2451, 98.4867) centre (6.4973, 87.5544) ccw
  arc A47 (22.0699, 100.1042) -> (23.2451, 98.4867) centre (22.6777, 99.3101) ccw
  arc A48 (22.0699, 100.1042) -> (21.3287, 100.972) centre (6.4973, 87.5544) ccw
  arc A49 (19.9149, 102.3858) -> (21.3287, 100.972) centre (20.6395, 101.6966) ccw
  arc A50 (19.9149, 102.3858) -> (19.0471, 103.127) centre (6.4973, 87.5544) ccw
  arc A51 (17.4296, 104.3022) -> (19.0471, 103.127) centre (18.2531, 103.7348) ccw
  arc A52 (17.4296, 104.3022) -> (16.4565, 104.8984) centre (6.4973, 87.5544) ccw
  arc A53 (14.6751, 105.8061) -> (16.4565, 104.8984) centre (15.5772, 105.3746) ccw
  arc A54 (14.6751, 105.8061) -> (13.6207, 106.2429) centre (6.4973, 87.5544) ccw
  arc A55 (11.7192, 106.8607) -> (13.6207, 106.2429) centre (12.6777, 106.5756) ccw
  arc A56 (11.7192, 106.8607) -> (10.6095, 107.1271) centre (6.4973, 87.5544) ccw
  arc A57 (8.6347, 107.4399) -> (10.6095, 107.1271) centre (9.626, 107.3082) ccw
  arc A58 (8.6347, 107.4399) -> (7.497, 107.5294) centre (6.4973, 87.5544) ccw
  arc A59 (5.4977, 107.5294) -> (7.497, 107.5294) centre (6.4973, 107.5544) ccw
  arc A60 (5.4977, 107.5294) -> (4.3599, 107.4399) centre (6.4973, 87.5544) ccw
  arc A61 (2.3852, 107.1271) -> (4.3599, 107.4399) centre (3.3687, 107.3082) ccw
  arc A62 (2.3852, 107.1271) -> (1.2755, 106.8607) centre (6.4973, 87.5544) ccw
  arc A63 (-0.626, 106.2429) -> (1.2755, 106.8607) centre (0.317, 106.5756) ccw
  arc A64 (-0.626, 106.2429) -> (-1.6804, 105.8061) centre (6.4973, 87.5544) ccw
  arc A65 (-3.4618, 104.8984) -> (-1.6804, 105.8061) centre (-2.5825, 105.3746) ccw
  arc A66 (-3.4618, 104.8984) -> (-4.4349, 104.3022) centre (6.4973, 87.5544) ccw
  arc A67 (-6.0524, 103.127) -> (-4.4349, 104.3022) centre (-5.2584, 103.7348) ccw
  arc A68 (-6.0524, 103.127) -> (-6.9202, 102.3858) centre (6.4973, 87.5544) ccw
  arc A69 (-8.334, 100.972) -> (-6.9202, 102.3858) centre (-7.6448, 101.6966) ccw
  arc A70 (-8.334, 100.972) -> (-9.0752, 100.1042) centre (6.4973, 87.5544) ccw
  arc A71 (-10.2504, 98.4867) -> (-9.0752, 100.1042) centre (-9.683, 99.3101) ccw
  arc A72 (-10.2504, 98.4867) -> (-10.8467, 97.5136) centre (6.4973, 87.5544) ccw
  arc A73 (-11.7544, 95.7322) -> (-10.8467, 97.5136) centre (-11.3228, 96.6343) ccw
  arc A74 (-11.7544, 95.7322) -> (-12.1911, 94.6778) centre (6.4973, 87.5544) ccw
  arc A75 (-12.8089, 92.7763) -> (-12.1911, 94.6778) centre (-12.5238, 93.7348) ccw
  arc A76 (-12.8089, 92.7763) -> (-13.0753, 91.6666) centre (6.4973, 87.5544) ccw
  arc A77 (-13.3881, 89.6918) -> (-13.0753, 91.6666) centre (-13.2564, 90.6831) ccw
  arc A78 (-13.3881, 89.6918) -> (-13.4777, 88.5541) centre (6.4973, 87.5544) ccw
  arc A79 (-13.4777, 86.5548) -> (-13.4777, 88.5541) centre (-13.5027, 87.5544) ccw
  line L0 (0.883, 100.4788) -> (1.2594, 99.8269)
  arc A80 (1.2594, 99.8269) -> (2.4492, 99.3808) centre (2.1254, 100.3269) ccw
  arc A81 (10.5455, 99.3808) -> (2.4492, 99.3808) centre (6.4973, 87.5544) ccw
  arc A82 (10.5455, 99.3808) -> (11.7353, 99.8269) centre (10.8693, 100.3269) ccw
  line L1 (11.7353, 99.8269) -> (12.1117, 100.4788)
  arc A83 (12.1117, 100.4788) -> (11.7457, 101.8448) centre (11.2457, 100.9788) ccw
  line L2 (11.7457, 101.8448) -> (11.3993, 102.0448)
  arc A84 (11.0332, 103.4108) -> (11.3993, 102.0448) centre (11.8993, 102.9108) ccw
  line L3 (11.0332, 103.4108) -> (11.2332, 103.7573)
  arc A85 (12.5993, 104.1233) -> (11.2332, 103.7573) centre (12.0993, 103.2573) ccw
  line L4 (12.5993, 104.1233) -> (17.7954, 101.1233)
  arc A86 (18.1614, 99.7573) -> (17.7954, 101.1233) centre (17.2954, 100.2573) ccw
  line L5 (18.1614, 99.7573) -> (17.9614, 99.4108)
  arc A87 (16.5954, 99.0448) -> (17.9614, 99.4108) centre (17.0954, 99.9108) ccw
  line L6 (16.5954, 99.0448) -> (16.249, 99.2448)
  arc A88 (16.249, 99.2448) -> (14.883, 98.8788) centre (15.749, 98.3788) ccw
  line L7 (14.883, 98.8788) -> (14.5066, 98.2269)
  arc A89 (14.5066, 98.2269) -> (14.7152, 96.9734) centre (15.3726, 97.7269) ccw
  arc A90 (18.7633, 89.9618) -> (14.7152, 96.9734) centre (6.4973, 87.5544) ccw
  arc A91 (18.7633, 89.9618) -> (19.7446, 89.1544) centre (19.7446, 90.1544) ccw
  line L8 (19.7446, 89.1544) -> (20.4973, 89.1544)
  arc A92 (20.4973, 89.1544) -> (21.4973, 90.1544) centre (20.4973, 90.1544) ccw
  line L9 (21.4973, 90.1544) -> (21.4973, 90.5544)
  arc A93 (22.4973, 91.5544) -> (21.4973, 90.5544) centre (22.4973, 90.5544) ccw
  line L10 (22.4973, 91.5544) -> (22.8973, 91.5544)
  arc A94 (23.8973, 90.5544) -> (22.8973, 91.5544) centre (22.8973, 90.5544) ccw
  line L11 (23.8973, 90.5544) -> (23.8973, 84.5544)
  arc A95 (22.8973, 83.5544) -> (23.8973, 84.5544) centre (22.8973, 84.5544) ccw
  line L12 (22.8973, 83.5544) -> (22.4973, 83.5544)
  arc A96 (21.4973, 84.5544) -> (22.4973, 83.5544) centre (22.4973, 84.5544) ccw
  line L13 (21.4973, 84.5544) -> (21.4973, 84.9544)
  arc A97 (21.4973, 84.9544) -> (20.4973, 85.9544) centre (20.4973, 84.9544) ccw
  line L14 (20.4973, 85.9544) -> (19.7446, 85.9544)
  arc A98 (19.7446, 85.9544) -> (18.7633, 85.147) centre (19.7446, 84.9544) ccw
  arc A99 (14.7152, 78.1355) -> (18.7633, 85.147) centre (6.4973, 87.5544) ccw
  arc A100 (14.7152, 78.1355) -> (14.5066, 76.882) centre (15.3726, 77.382) ccw
  line L15 (14.5066, 76.882) -> (14.883, 76.2301)
  arc A101 (14.883, 76.2301) -> (16.249, 75.8641) centre (15.749, 76.7301) ccw
  line L16 (16.249, 75.8641) -> (16.5954, 76.0641)
  arc A102 (17.9614, 75.698) -> (16.5954, 76.0641) centre (17.0954, 75.198) ccw
  line L17 (17.9614, 75.698) -> (18.1614, 75.3516)
  arc A103 (17.7954, 73.9856) -> (18.1614, 75.3516) centre (17.2954, 74.8516) ccw
  line L18 (17.7954, 73.9856) -> (12.5993, 70.9856)
  arc A104 (11.2332, 71.3516) -> (12.5993, 70.9856) centre (12.0993, 71.8516) ccw
  line L19 (11.2332, 71.3516) -> (11.0332, 71.698)
  arc A105 (11.3993, 73.0641) -> (11.0332, 71.698) centre (11.8993, 72.198) ccw
  line L20 (11.3993, 73.0641) -> (11.7457, 73.2641)
  arc A106 (11.7457, 73.2641) -> (12.1117, 74.6301) centre (11.2457, 74.1301) ccw
  line L21 (12.1117, 74.6301) -> (11.7353, 75.282)
  arc A107 (11.7353, 75.282) -> (10.5455, 75.7281) centre (10.8693, 74.782) ccw
  arc A108 (2.4492, 75.7281) -> (10.5455, 75.7281) centre (6.4973, 87.5544) ccw
  arc A109 (2.4492, 75.7281) -> (1.2594, 75.282) centre (2.1254, 74.782) ccw
  line L22 (1.2594, 75.282) -> (0.883, 74.6301)
  arc A110 (0.883, 74.6301) -> (1.249, 73.2641) centre (1.749, 74.1301) ccw
  line L23 (1.249, 73.2641) -> (1.5954, 73.0641)
  arc A111 (1.9614, 71.698) -> (1.5954, 73.0641) centre (1.0954, 72.198) ccw
  line L24 (1.9614, 71.698) -> (1.7614, 71.3516)
  arc A112 (0.3954, 70.9856) -> (1.7614, 71.3516) centre (0.8954, 71.8516) ccw
  line L25 (0.3954, 70.9856) -> (-4.8007, 73.9856)
  arc A113 (-5.1668, 75.3516) -> (-4.8007, 73.9856) centre (-4.3007, 74.8516) ccw
  line L26 (-5.1668, 75.3516) -> (-4.9668, 75.698)
  arc A114 (-3.6007, 76.0641) -> (-4.9668, 75.698) centre (-4.1007, 75.198) ccw
  line L27 (-3.6007, 76.0641) -> (-3.2543, 75.8641)
  arc A115 (-3.2543, 75.8641) -> (-1.8883, 76.2301) centre (-2.7543, 76.7301) ccw
  line L28 (-1.8883, 76.2301) -> (-1.5119, 76.882)
  arc A116 (-1.5119, 76.882) -> (-1.7205, 78.1355) centre (-2.378, 77.382) ccw
  arc A117 (-5.7686, 85.147) -> (-1.7205, 78.1355) centre (6.4973, 87.5544) ccw
  arc A118 (-5.7686, 85.147) -> (-6.7499, 85.9544) centre (-6.7499, 84.9544) ccw
  line L29 (-6.7499, 85.9544) -> (-7.5027, 85.9544)
  arc A119 (-7.5027, 85.9544) -> (-8.5027, 84.9544) centre (-7.5027, 84.9544) ccw
  line L30 (-8.5027, 84.9544) -> (-8.5027, 84.5544)
  arc A120 (-9.5027, 83.5544) -> (-8.5027, 84.5544) centre (-9.5027, 84.5544) ccw
  line L31 (-9.5027, 83.5544) -> (-9.9027, 83.5544)
  arc A121 (-10.9027, 84.5544) -> (-9.9027, 83.5544) centre (-9.9027, 84.5544) ccw
  line L32 (-10.9027, 84.5544) -> (-10.9027, 90.5544)
  arc A122 (-9.9027, 91.5544) -> (-10.9027, 90.5544) centre (-9.9027, 90.5544) ccw
  line L33 (-9.9027, 91.5544) -> (-9.5027, 91.5544)
  arc A123 (-8.5027, 90.5544) -> (-9.5027, 91.5544) centre (-9.5027, 90.5544) ccw
  line L34 (-8.5027, 90.5544) -> (-8.5027, 90.1544)
  arc A124 (-8.5027, 90.1544) -> (-7.5027, 89.1544) centre (-7.5027, 90.1544) ccw
  line L35 (-7.5027, 89.1544) -> (-6.7499, 89.1544)
  arc A125 (-6.7499, 89.1544) -> (-5.7686, 89.9618) centre (-6.7499, 90.1544) ccw
  arc A126 (-1.7205, 96.9734) -> (-5.7686, 89.9618) centre (6.4973, 87.5544) ccw
  arc A127 (-1.7205, 96.9734) -> (-1.5119, 98.2269) centre (-2.378, 97.7269) ccw
  line L36 (-1.5119, 98.2269) -> (-1.8883, 98.8788)
  arc A128 (-1.8883, 98.8788) -> (-3.2543, 99.2448) centre (-2.7543, 98.3788) ccw
  line L37 (-3.2543, 99.2448) -> (-3.6007, 99.0448)
  arc A129 (-4.9668, 99.4108) -> (-3.6007, 99.0448) centre (-4.1007, 99.9108) ccw
  line L38 (-4.9668, 99.4108) -> (-5.1668, 99.7573)
  arc A130 (-4.8007, 101.1233) -> (-5.1668, 99.7573) centre (-4.3007, 100.2573) ccw
  line L39 (-4.8007, 101.1233) -> (0.3954, 104.1233)
  arc A131 (1.7614, 103.7573) -> (0.3954, 104.1233) centre (0.8954, 103.2573) ccw
  line L40 (1.7614, 103.7573) -> (1.9614, 103.4108)
  arc A132 (1.5954, 102.0448) -> (1.9614, 103.4108) centre (1.0954, 102.9108) ccw
  line L41 (1.5954, 102.0448) -> (1.249, 101.8448)
  arc A133 (1.249, 101.8448) -> (0.883, 100.4788) centre (1.749, 100.9788) ccw
  circle A134 centre (6.4973, 87.5544) radius 21.5
  circle A135 centre (-15.0027, 87.5544) radius 1
  circle A136 centre (-14.738, 84.1911) radius 1
  circle A137 centre (-13.9504, 80.9106) radius 1
  circle A138 centre (-12.6593, 77.7936) radius 1
  circle A139 centre (-10.8965, 74.9171) radius 1
  circle A140 centre (-8.7054, 72.3516) radius 1
  circle A141 centre (-6.14, 70.1606) radius 1
  circle A142 centre (-3.2634, 68.3978) radius 1
  circle A143 centre (-0.1465, 67.1067) radius 1
  circle A144 centre (3.134, 66.3191) radius 1
  circle A145 centre (6.4973, 66.0544) radius 1
  circle A146 centre (9.8607, 66.3191) radius 1
  circle A147 centre (13.1412, 67.1067) radius 1
  circle A148 centre (16.2581, 68.3978) radius 1
  circle A149 centre (19.1347, 70.1606) radius 1
  circle A150 centre (21.7001, 72.3516) radius 1
  circle A151 centre (23.8912, 74.9171) radius 1
  circle A152 centre (25.654, 77.7936) radius 1
  circle A153 centre (26.9451, 80.9106) radius 1
  circle A154 centre (27.7326, 84.1911) radius 1
  circle A155 centre (27.9973, 87.5544) radius 1
  circle A156 centre (27.7326, 90.9178) radius 1
  circle A157 centre (26.9451, 94.1983) radius 1
  circle A158 centre (25.654, 97.3152) radius 1
  circle A159 centre (23.8912, 100.1918) radius 1
  circle A160 centre (21.7001, 102.7572) radius 1
  circle A161 centre (19.1347, 104.9483) radius 1
  circle A162 centre (16.2581, 106.7111) radius 1
  circle A163 centre (13.1412, 108.0022) radius 1
  circle A164 centre (9.8607, 108.7897) radius 1
  circle A165 centre (6.4973, 109.0544) radius 1
  circle A166 centre (3.134, 108.7897) radius 1
  circle A167 centre (-0.1465, 108.0022) radius 1
  circle A168 centre (-3.2634, 106.7111) radius 1
  circle A169 centre (-6.14, 104.9483) radius 1
  circle A170 centre (-8.7054, 102.7572) radius 1
  circle A171 centre (-10.8965, 100.1918) radius 1
  circle A172 centre (-12.6593, 97.3152) radius 1
  circle A173 centre (-13.9504, 94.1983) radius 1
  circle A174 centre (-14.738, 90.9178) radius 1
  circle A175 centre (-0.2217, 0) radius 6.5 projected
  line L42 (3.8, 2.4104) -> (3.8, -2.4104) projected
  arc A176 (3.8, 2.4104) -> (3.8, -2.4104) centre (0, 0) ccw projected
  arc A177 (-19.975, -0.9997) -> (-19.8855, -2.1374) centre (0, 0) ccw
  arc A178 (-19.5727, -4.1122) -> (-19.8855, -2.1374) centre (-19.7538, -3.1287) ccw
  arc A179 (-19.5727, -4.1122) -> (-19.3063, -5.2219) centre (0, 0) ccw
  arc A180 (-18.6884, -7.1234) -> (-19.3063, -5.2219) centre (-19.0211, -6.1803) ccw
  arc A181 (-18.6884, -7.1234) -> (-18.2517, -8.1777) centre (0, 0) ccw
  arc A182 (-17.344, -9.9592) -> (-18.2517, -8.1777) centre (-17.8201, -9.0798) ccw
  arc A183 (-17.344, -9.9592) -> (-16.7477, -10.9322) centre (0, 0) ccw
  arc A184 (-15.5725, -12.5498) -> (-16.7477, -10.9322) centre (-16.1803, -11.7557) ccw
  arc A185 (-15.5725, -12.5498) -> (-14.8313, -13.4176) centre (0, 0) ccw
  arc A186 (-13.4176, -14.8313) -> (-14.8313, -13.4176) centre (-14.1421, -14.1421) ccw
  arc A187 (-13.4176, -14.8313) -> (-12.5498, -15.5725) centre (0, 0) ccw
  arc A188 (-10.9322, -16.7477) -> (-12.5498, -15.5725) centre (-11.7557, -16.1803) ccw
  arc A189 (-10.9322, -16.7477) -> (-9.9592, -17.344) centre (0, 0) ccw
  arc A190 (-8.1777, -18.2517) -> (-9.9592, -17.344) centre (-9.0798, -17.8201) ccw
  arc A191 (-8.1777, -18.2517) -> (-7.1234, -18.6884) centre (0, 0) ccw
  arc A192 (-5.2219, -19.3063) -> (-7.1234, -18.6884) centre (-6.1803, -19.0211) ccw
  arc A193 (-5.2219, -19.3063) -> (-4.1122, -19.5727) centre (0, 0) ccw
  arc A194 (-2.1374, -19.8855) -> (-4.1122, -19.5727) centre (-3.1287, -19.7538) ccw
  arc A195 (-2.1374, -19.8855) -> (-0.9997, -19.975) centre (0, 0) ccw
  arc A196 (0.9997, -19.975) -> (-0.9997, -19.975) centre (0, -20) ccw
  arc A197 (0.9997, -19.975) -> (2.1374, -19.8855) centre (0, 0) ccw
  arc A198 (4.1122, -19.5727) -> (2.1374, -19.8855) centre (3.1287, -19.7538) ccw
  arc A199 (4.1122, -19.5727) -> (5.2219, -19.3063) centre (0, 0) ccw
  arc A200 (7.1234, -18.6884) -> (5.2219, -19.3063) centre (6.1803, -19.0211) ccw
  arc A201 (7.1234, -18.6884) -> (8.1777, -18.2517) centre (0, 0) ccw
  arc A202 (9.9592, -17.344) -> (8.1777, -18.2517) centre (9.0798, -17.8201) ccw